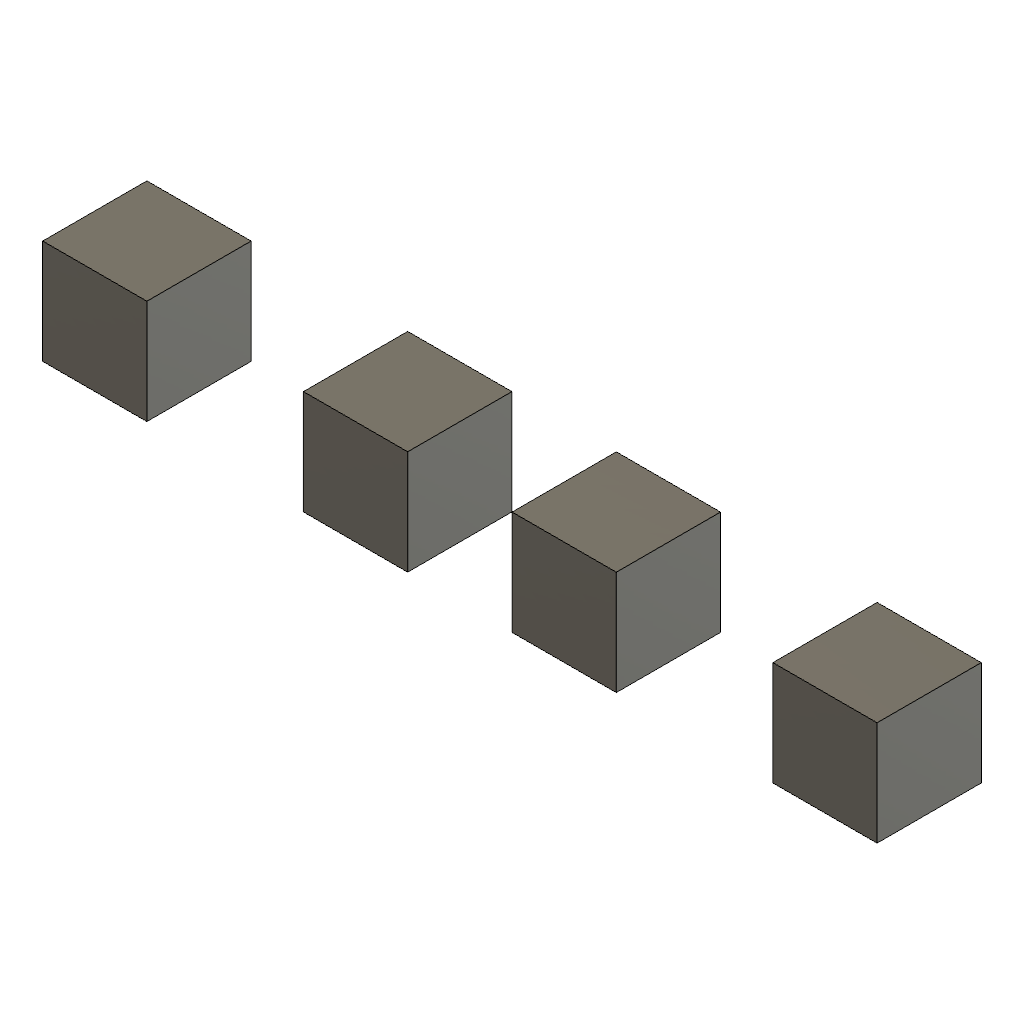
mirror_two_features (Autodesk Fusion 360 design; units mm, degrees)
part number: 2026-10-20-23-50-05-645
Autodesk Fusion 360 part; units mm, degrees
sketch "FeatureInputSketch1" plane through (0, 0, 0) normal (0, 0, 1) x (1, 0, 0)
  line L0 (10, 10) -> (30, 10)
  line L1 (30, 10) -> (30, 30)
  line L2 (30, 30) -> (10, 30)
  line L3 (10, 30) -> (10, 10)
extrude "FeatureInputExtrude1" add sketch "FeatureInputSketch1" along normal blind 20 makes body 1
sketch "FeatureInputSketch2" plane through (0, 0, 0) normal (0, 0, 1) x (1, 0, 0)
  line L0 (60, 10) -> (80, 10)
  line L1 (80, 10) -> (80, 30)
  line L2 (80, 30) -> (60, 30)
  line L3 (60, 30) -> (60, 10)
extrude "FeatureInputExtrude2" add sketch "FeatureInputSketch2" along normal blind 20 separate body makes body 2
mirror "ProbeRemainingBodyInput" about plane through (0, 0, 0) normal (1, 0, 0) of "FeatureInputExtrude1", "FeatureInputExtrude2" makes body 3 at (-10, 23.3333, 6.6667) makes body 4 at (-60, 23.3333, 6.6667)
named bodies: "FeatureInputBody1", "FeatureInputBody2", "FeatureInputBody1 (1)", "FeatureInputBody2 (1)"
